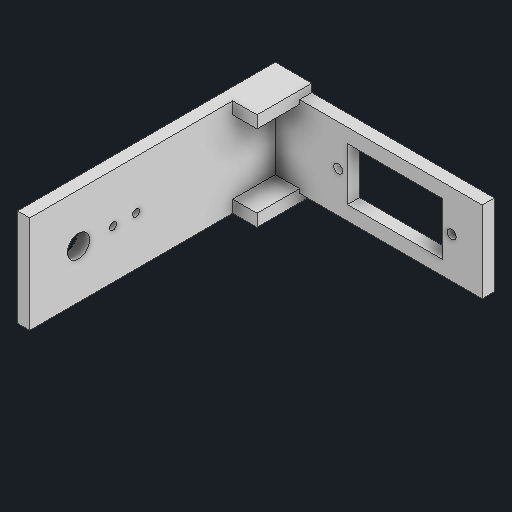
# Autodesk Inventor part: 04_Brazo_pitch
Saved by Autodesk Inventor 2027.2 (Build 312334000, 334)
## iProperties
Created: 2026-11-14
Part Number: 04_Brazo_pitch
Material: Genérico
Document SubType Name: Modeling
Designer: alexa
Density: 1 g/cm^3
Appearance: Valor por defecto
Mass: 7.05615 g
Surface Area: 58.8133 cm^2
Volume: 7.05615 cm^3
Author: alexa
Autodesk Inventor part; units mm, degrees
ref_plane "Placa_horn_pitch_perfil_plano" through (0, 0, -51.5) normal (0, 0, 1) x (1, 0, 0)
sketch "Placa_horn_pitch_perfil" plane through (0, 0, -51.5) normal (0, 0, 1) x (1, 0, 0)
  line L0 (-38, -12) -> (-35, -12)
  line L1 (-35, -12) -> (-35, 12)
  line L2 (-35, 12) -> (-38, 12)
  line L3 (-38, 12) -> (-38, -12)
  constraints: 8 end point, 2 parallel, 1 horizontal, 1 perpendicular
extrude "Placa_horn_pitch" add sketch "Placa_horn_pitch_perfil" along normal blind 63.5
ref_plane "Soporte_servo_roll_perfil_plano" through (0, 0, -51.5) normal (0, 0, 1) x (1, 0, 0)
sketch "Soporte_servo_roll_perfil" plane through (0, 0, -51.5) normal (0, 0, 1) x (1, 0, 0)
  line L0 (-38, -10) -> (16, -10)
  line L1 (16, -10) -> (16, 10)
  line L2 (16, 10) -> (-38, 10)
  line L3 (-38, 10) -> (-38, -10)
  constraints: 8 end point, 2 parallel, 1 horizontal, 1 perpendicular
extrude "Soporte_servo_roll" add sketch "Soporte_servo_roll_perfil" along normal blind 3
ref_plane "Paso_cuerpo_MG90S_perfil_plano" through (0, 0, -51.6) normal (0, 0, 1) x (1, 0, 0)
sketch "Paso_cuerpo_MG90S_perfil" plane through (0, 0, -51.6) normal (0, 0, 1) x (1, 0, 0)
  line L0 (-17.2, -6.5) -> (6.3, -6.5)
  line L1 (6.3, -6.5) -> (6.3, 6.5)
  line L2 (6.3, 6.5) -> (-17.2, 6.5)
  line L3 (-17.2, 6.5) -> (-17.2, -6.5)
  constraints: 8 end point, 2 parallel, 1 horizontal, 1 perpendicular
extrude "Paso_cuerpo_MG90S" cut sketch "Paso_cuerpo_MG90S_perfil" along normal blind 3.2
ref_plane "Fijacion_servo_-19.5_perfil_plano" through (0, 0, -51.7) normal (0, 0, 1) x (1, 0, 0)
sketch "Fijacion_servo_-19.5_perfil" plane through (0, 0, -51.7) normal (0, 0, 1) x (1, 0, 0)
  circle A0 centre (-19.5, 0) radius 1.1
  constraints: 1 centre point
extrude "Fijacion_servo_-19.5" cut sketch "Fijacion_servo_-19.5_perfil" along normal blind 3.4
ref_plane "Fijacion_servo_8.5_perfil_plano" through (0, 0, -51.7) normal (0, 0, 1) x (1, 0, 0)
sketch "Fijacion_servo_8.5_perfil" plane through (0, 0, -51.7) normal (0, 0, 1) x (1, 0, 0)
  circle A0 centre (8.5, 0) radius 1.1
  constraints: 1 centre point
extrude "Fijacion_servo_8.5" cut sketch "Fijacion_servo_8.5_perfil" along normal blind 3.4
ref_plane "Acceso_tornillo_central_horn_perfil_plano" through (-38.1, 0, 0) normal (1, 0, 0) x (0, 1, 0)
sketch "Acceso_tornillo_central_horn_perfil" plane through (-38.1, 0, 0) normal (1, 0, 0) x (0, 1, 0)
  circle A0 centre (0, 0) radius 2.75
  constraints: 1 centre point
extrude "Acceso_tornillo_central_horn" cut sketch "Acceso_tornillo_central_horn_perfil" along normal blind 3.2
ref_plane "Paso_horn_r_8.5_perfil_plano" through (-38.1, 0, 0) normal (1, 0, 0) x (0, 1, 0)
sketch "Paso_horn_r_8.5_perfil" plane through (-38.1, 0, 0) normal (1, 0, 0) x (0, 1, 0)
  circle A0 centre (0, -8.5) radius 0.9
  constraints: 1 centre point
extrude "Paso_horn_r_8.5" cut sketch "Paso_horn_r_8.5_perfil" along normal blind 3.2
ref_plane "Paso_horn_r_14.2_perfil_plano" through (-38.1, 0, 0) normal (1, 0, 0) x (0, 1, 0)
sketch "Paso_horn_r_14.2_perfil" plane through (-38.1, 0, 0) normal (1, 0, 0) x (0, 1, 0)
  circle A0 centre (0, -14.2) radius 0.9
  constraints: 1 centre point
extrude "Paso_horn_r_14.2" cut sketch "Paso_horn_r_14.2_perfil" along normal blind 3.2
ref_plane "Nervio_inferior_perfil_plano" through (0, 0, -51.5) normal (0, 0, 1) x (1, 0, 0)
sketch "Nervio_inferior_perfil" plane through (0, 0, -51.5) normal (0, 0, 1) x (1, 0, 0)
  line L0 (-35, -12) -> (-29, -12)
  line L1 (-29, -12) -> (-29, -9)
  line L2 (-29, -9) -> (-35, -9)
  line L3 (-35, -9) -> (-35, -12)
  constraints: 8 end point, 2 parallel, 1 horizontal, 1 perpendicular
extrude "Nervio_inferior" add sketch "Nervio_inferior_perfil" along normal blind 13.5
ref_plane "Nervio_superior_perfil_plano" through (0, 0, -51.5) normal (0, 0, 1) x (1, 0, 0)
sketch "Nervio_superior_perfil" plane through (0, 0, -51.5) normal (0, 0, 1) x (1, 0, 0)
  line L0 (-35, 9) -> (-29, 9)
  line L1 (-29, 9) -> (-29, 12)
  line L2 (-29, 12) -> (-35, 12)
  line L3 (-35, 12) -> (-35, 9)
  constraints: 8 end point, 2 parallel, 1 horizontal, 1 perpendicular
extrude "Nervio_superior" add sketch "Nervio_superior_perfil" along normal blind 13.5
ref_plane "Pitch_apoyo" through (-38, 0, 0) normal (1, 0, 0) x (0, 1, 0)
ref_plane "Roll_apoyo" through (0, 0, -34) normal (0, 0, 1) x (1, 0, 0)
ref_plane "Servo_roll_ref_1" through (0, 0, -48.5) normal (1, 0, 0) x (0, 1, 0)
ref_plane "Servo_roll_ref_2" through (0, 0, -48.5) normal (0, 1, 0) x (1, 0, 0)
ref_plane "Servo_roll_ref_3" through (0, 0, -48.5) normal (0, 0, 1) x (1, 0, 0)
ref_plane "Horn_pitch_ref_1" through (-38, 0, 0) normal (-1, 0, 0) x (0, 1, 0)
ref_plane "Horn_pitch_ref_2" through (-38, 0, 0) normal (0, 0, -1) x (1, 0, 0)
ref_plane "Horn_pitch_ref_3" through (-38, 0, 0) normal (0, -1, 0) x (1, 0, 0)
